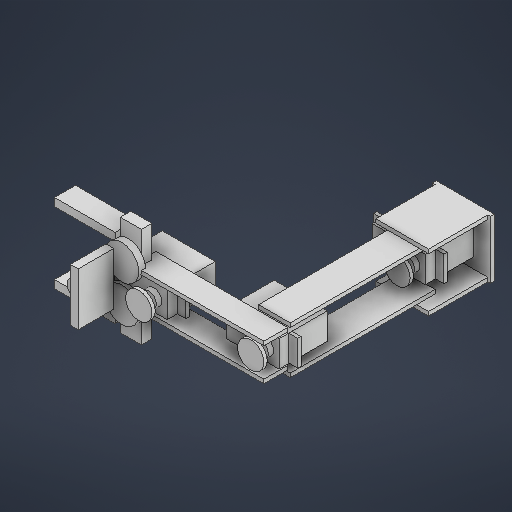
# Autodesk Inventor part: 05_Canh_Tay_3xMG996R_180_Kep_Banh_Rang_ESP32CAM
Saved by Autodesk Inventor 2027.1 (Build 311270010, 270A)
## iProperties
Created: 2026-11-18
Part Number: 05_Canh_Tay_3xMG996R_180_Kep_Banh_Rang_ESP32CAM
Material: Generic
Document SubType Name: Modeling
Designer: cuong
Density: 1 g/cm^3
Appearance: Default
Author: cuong
Autodesk Inventor part; units mm, degrees
ref_plane "Work Plane1" through (0, 0, 185) normal (0, 0, 1) x (1, 0, 0)
sketch "Sketch1" plane through (0, 0, 185) normal (0, 0, 1) x (1, 0, 0)
  line L0 (23, 103) -> (67, 103)
  line L1 (67, 103) -> (67, 147)
  line L2 (67, 147) -> (23, 147)
  line L3 (23, 147) -> (23, 103)
  constraints: 8 end point, 2 parallel, 1 horizontal, 1 perpendicular
extrude "Extrusion1" add sketch "Sketch1" along normal blind 3
ref_plane "Work Plane2" through (0, 0, 188) normal (0, 0, 1) x (1, 0, 0)
sketch "Sketch2" plane through (0, 0, 188) normal (0, 0, 1) x (1, 0, 0)
  line L0 (25, 103) -> (65, 103)
  line L1 (65, 103) -> (65, 106)
  line L2 (65, 106) -> (25, 106)
  line L3 (25, 106) -> (25, 103)
  constraints: 8 end point, 2 parallel, 1 horizontal, 1 perpendicular
extrude "Extrusion2" add sketch "Sketch2" along normal blind 45
ref_plane "Work Plane3" through (0, 0, 188) normal (0, 0, 1) x (1, 0, 0)
sketch "Sketch3" plane through (0, 0, 188) normal (0, 0, 1) x (1, 0, 0)
  line L0 (25, 144) -> (65, 144)
  line L1 (65, 144) -> (65, 147)
  line L2 (65, 147) -> (25, 147)
  line L3 (25, 147) -> (25, 144)
  constraints: 8 end point, 2 parallel, 1 horizontal, 1 perpendicular
extrude "Extrusion3" add sketch "Sketch3" along normal blind 45
ref_plane "Work Plane4" through (0, 0, 189) normal (0, 0, 1) x (1, 0, 0)
sketch "Sketch4" plane through (0, 0, 189) normal (0, 0, 1) x (1, 0, 0)
  line L0 (14.85, 115) -> (55.15, 115)
  line L1 (55.15, 115) -> (55.15, 135)
  line L2 (55.15, 135) -> (14.85, 135)
  line L3 (14.85, 135) -> (14.85, 115)
  constraints: 8 end point, 2 parallel, 1 horizontal, 1 perpendicular
extrude "Extrusion4" add sketch "Sketch4" along normal blind 36.6
ref_plane "Work Plane5" through (0, 0, 215.6) normal (0, 0, 1) x (1, 0, 0)
sketch "Sketch5" plane through (0, 0, 215.6) normal (0, 0, 1) x (1, 0, 0)
  line L0 (8.2, 115.25) -> (61.8, 115.25)
  line L1 (61.8, 115.25) -> (61.8, 134.75)
  line L2 (61.8, 134.75) -> (8.2, 134.75)
  line L3 (8.2, 134.75) -> (8.2, 115.25)
  constraints: 8 end point, 2 parallel, 1 horizontal, 1 perpendicular
extrude "Extrusion5" add sketch "Sketch5" along normal blind 2.5
ref_plane "Work Plane6" through (0, 0, 225.6) normal (0, 0, 1) x (1, 0, 0)
sketch "Sketch6" plane through (0, 0, 225.6) normal (0, 0, 1) x (1, 0, 0)
  circle A0 centre (45, 125) radius 6
  constraints: 1 centre point
extrude "Extrusion6" add sketch "Sketch6" along normal blind 4
ref_plane "Work Plane7" through (0, 0, 229.6) normal (0, 0, 1) x (1, 0, 0)
sketch "Sketch7" plane through (0, 0, 229.6) normal (0, 0, 1) x (1, 0, 0)
  circle A0 centre (45, 125) radius 3
  constraints: 1 centre point
extrude "Extrusion7" add sketch "Sketch7" along normal blind 7
ref_plane "Work Plane8" through (0, 0, 234.5) normal (0, 0, 1) x (1, 0, 0)
sketch "Sketch8" plane through (0, 0, 234.5) normal (0, 0, 1) x (1, 0, 0)
  circle A0 centre (45, 125) radius 10
  constraints: 1 centre point
extrude "Extrusion8" add sketch "Sketch8" along normal blind 2.5
ref_plane "Work Plane9" through (0, 0, 220) normal (0, 0, 1) x (1, 0, 0)
sketch "Sketch9" plane through (0, 0, 220) normal (0, 0, 1) x (1, 0, 0)
  line L0 (33, 107) -> (57, 107)
  line L1 (57, 107) -> (57, 110)
  line L2 (57, 110) -> (33, 110)
  line L3 (33, 110) -> (33, 107)
  constraints: 8 end point, 2 parallel, 1 horizontal, 1 perpendicular
extrude "Extrusion9" add sketch "Sketch9" along normal blind 110
ref_plane "Work Plane10" through (0, 0, 220) normal (0, 0, 1) x (1, 0, 0)
sketch "Sketch10" plane through (0, 0, 220) normal (0, 0, 1) x (1, 0, 0)
  line L0 (33, 140) -> (57, 140)
  line L1 (57, 140) -> (57, 143)
  line L2 (57, 143) -> (33, 143)
  line L3 (33, 143) -> (33, 140)
  constraints: 8 end point, 2 parallel, 1 horizontal, 1 perpendicular
extrude "Extrusion10" add sketch "Sketch10" along normal blind 110
ref_plane "Work Plane11" through (0, 0, 300) normal (0, 0, 1) x (1, 0, 0)
sketch "Sketch11" plane through (0, 0, 300) normal (0, 0, 1) x (1, 0, 0)
  line L0 (14.85, 115) -> (55.15, 115)
  line L1 (55.15, 115) -> (55.15, 135)
  line L2 (55.15, 135) -> (14.85, 135)
  line L3 (14.85, 135) -> (14.85, 115)
  constraints: 8 end point, 2 parallel, 1 horizontal, 1 perpendicular
extrude "Extrusion11" add sketch "Sketch11" along normal blind 36.6
ref_plane "Work Plane12" through (0, 0, 326.6) normal (0, 0, 1) x (1, 0, 0)
sketch "Sketch12" plane through (0, 0, 326.6) normal (0, 0, 1) x (1, 0, 0)
  line L0 (8.2, 115.25) -> (61.8, 115.25)
  line L1 (61.8, 115.25) -> (61.8, 134.75)
  line L2 (61.8, 134.75) -> (8.2, 134.75)
  line L3 (8.2, 134.75) -> (8.2, 115.25)
  constraints: 8 end point, 2 parallel, 1 horizontal, 1 perpendicular
extrude "Extrusion12" add sketch "Sketch12" along normal blind 2.5
ref_plane "Work Plane13" through (0, 0, 336.6) normal (0, 0, 1) x (1, 0, 0)
sketch "Sketch13" plane through (0, 0, 336.6) normal (0, 0, 1) x (1, 0, 0)
  circle A0 centre (45, 125) radius 6
  constraints: 1 centre point
extrude "Extrusion13" add sketch "Sketch13" along normal blind 4
ref_plane "Work Plane14" through (0, 0, 340.6) normal (0, 0, 1) x (1, 0, 0)
sketch "Sketch14" plane through (0, 0, 340.6) normal (0, 0, 1) x (1, 0, 0)
  circle A0 centre (45, 125) radius 3
  constraints: 1 centre point
extrude "Extrusion14" add sketch "Sketch14" along normal blind 7
ref_plane "Work Plane15" through (0, 0, 345.5) normal (0, 0, 1) x (1, 0, 0)
sketch "Sketch15" plane through (0, 0, 345.5) normal (0, 0, 1) x (1, 0, 0)
  circle A0 centre (45, 125) radius 10
  constraints: 1 centre point
extrude "Extrusion15" add sketch "Sketch15" along normal blind 2.5
ref_plane "Work Plane16" through (0, 0, 330) normal (0, 0, 1) x (1, 0, 0)
sketch "Sketch16" plane through (0, 0, 330) normal (0, 0, 1) x (1, 0, 0)
  line L0 (-45, 111) -> (55, 111)
  line L1 (55, 111) -> (55, 114)
  line L2 (55, 114) -> (-45, 114)
  line L3 (-45, 114) -> (-45, 111)
  constraints: 8 end point, 2 parallel, 1 horizontal, 1 perpendicular
extrude "Extrusion16" add sketch "Sketch16" along normal blind 18
ref_plane "Work Plane17" through (0, 0, 330) normal (0, 0, 1) x (1, 0, 0)
sketch "Sketch17" plane through (0, 0, 330) normal (0, 0, 1) x (1, 0, 0)
  line L0 (-45, 136) -> (55, 136)
  line L1 (55, 136) -> (55, 139)
  line L2 (55, 139) -> (-45, 139)
  line L3 (-45, 139) -> (-45, 136)
  constraints: 8 end point, 2 parallel, 1 horizontal, 1 perpendicular
extrude "Extrusion17" add sketch "Sketch17" along normal blind 18
ref_plane "Work Plane18" through (0, 0, 310) normal (0, 0, 1) x (1, 0, 0)
sketch "Sketch18" plane through (0, 0, 310) normal (0, 0, 1) x (1, 0, 0)
  line L0 (-60.15, 115) -> (-19.85, 115)
  line L1 (-19.85, 115) -> (-19.85, 135)
  line L2 (-19.85, 135) -> (-60.15, 135)
  line L3 (-60.15, 135) -> (-60.15, 115)
  constraints: 8 end point, 2 parallel, 1 horizontal, 1 perpendicular
extrude "Extrusion18" add sketch "Sketch18" along normal blind 36.6
ref_plane "Work Plane19" through (0, 0, 336.6) normal (0, 0, 1) x (1, 0, 0)
sketch "Sketch19" plane through (0, 0, 336.6) normal (0, 0, 1) x (1, 0, 0)
  line L0 (-66.8, 115.25) -> (-13.2, 115.25)
  line L1 (-13.2, 115.25) -> (-13.2, 134.75)
  line L2 (-13.2, 134.75) -> (-66.8, 134.75)
  line L3 (-66.8, 134.75) -> (-66.8, 115.25)
  constraints: 8 end point, 2 parallel, 1 horizontal, 1 perpendicular
extrude "Extrusion19" add sketch "Sketch19" along normal blind 2.5
ref_plane "Work Plane20" through (0, 0, 346.6) normal (0, 0, 1) x (1, 0, 0)
sketch "Sketch20" plane through (0, 0, 346.6) normal (0, 0, 1) x (1, 0, 0)
  circle A0 centre (-30, 125) radius 6
  constraints: 1 centre point
extrude "Extrusion20" add sketch "Sketch20" along normal blind 4
ref_plane "Work Plane21" through (0, 0, 350.6) normal (0, 0, 1) x (1, 0, 0)
sketch "Sketch21" plane through (0, 0, 350.6) normal (0, 0, 1) x (1, 0, 0)
  circle A0 centre (-30, 125) radius 3
  constraints: 1 centre point
extrude "Extrusion21" add sketch "Sketch21" along normal blind 7
ref_plane "Work Plane22" through (0, 0, 355.5) normal (0, 0, 1) x (1, 0, 0)
sketch "Sketch22" plane through (0, 0, 355.5) normal (0, 0, 1) x (1, 0, 0)
  circle A0 centre (-30, 125) radius 10
  constraints: 1 centre point
extrude "Extrusion22" add sketch "Sketch22" along normal blind 2.5
ref_plane "Work Plane23" through (0, 0, 337) normal (0, 0, 1) x (1, 0, 0)
sketch "Sketch23" plane through (0, 0, 337) normal (0, 0, 1) x (1, 0, 0)
  line L0 (-57, 87) -> (-41, 87)
  line L1 (-41, 87) -> (-41, 163)
  line L2 (-41, 163) -> (-57, 163)
  line L3 (-57, 163) -> (-57, 87)
  constraints: 8 end point, 2 parallel, 1 horizontal, 1 perpendicular
extrude "Extrusion23" add sketch "Sketch23" along normal blind 8
ref_plane "Work Plane24" through (0, 0, 345) normal (0, 0, 1) x (1, 0, 0)
sketch "Sketch24" plane through (0, 0, 345) normal (0, 0, 1) x (1, 0, 0)
  circle A0 centre (-51, 111) radius 13
  constraints: 1 centre point
extrude "Extrusion24" add sketch "Sketch24" along normal blind 5
ref_plane "Work Plane25" through (0, 0, 345) normal (0, 0, 1) x (1, 0, 0)
sketch "Sketch25" plane through (0, 0, 345) normal (0, 0, 1) x (1, 0, 0)
  circle A0 centre (-51, 139) radius 13
  constraints: 1 centre point
extrude "Extrusion25" add sketch "Sketch25" along normal blind 5
ref_plane "Work Plane26" through (0, 0, 333) normal (0, 0, 1) x (1, 0, 0)
sketch "Sketch26" plane through (0, 0, 333) normal (0, 0, 1) x (1, 0, 0)
  line L0 (-103, 95) -> (-57, 95)
  line L1 (-57, 95) -> (-57, 101)
  line L2 (-57, 101) -> (-103, 101)
  line L3 (-103, 101) -> (-103, 95)
  constraints: 8 end point, 2 parallel, 1 horizontal, 1 perpendicular
extrude "Extrusion26" add sketch "Sketch26" along normal blind 16
ref_plane "Work Plane27" through (0, 0, 333) normal (0, 0, 1) x (1, 0, 0)
sketch "Sketch27" plane through (0, 0, 333) normal (0, 0, 1) x (1, 0, 0)
  line L0 (-103, 149) -> (-57, 149)
  line L1 (-57, 149) -> (-57, 155)
  line L2 (-57, 155) -> (-103, 155)
  line L3 (-103, 155) -> (-103, 149)
  constraints: 8 end point, 2 parallel, 1 horizontal, 1 perpendicular
extrude "Extrusion27" add sketch "Sketch27" along normal blind 16
ref_plane "Work Plane28" through (0, 0, 350) normal (0, 0, 1) x (1, 0, 0)
sketch "Sketch28" plane through (0, 0, 350) normal (0, 0, 1) x (1, 0, 0)
  line L0 (-63, 105) -> (-57, 105)
  line L1 (-57, 105) -> (-57, 145)
  line L2 (-57, 145) -> (-63, 145)
  line L3 (-63, 145) -> (-63, 105)
  constraints: 8 end point, 2 parallel, 1 horizontal, 1 perpendicular
extrude "Extrusion28" add sketch "Sketch28" along normal blind 27
ref_plane "Work Plane29" through (0, 0, 359) normal (0, 0, 1) x (1, 0, 0)
sketch "Sketch29" plane through (0, 0, 359) normal (0, 0, 1) x (1, 0, 0)
  circle A0 centre (-65, 125) radius 6.5
  constraints: 1 centre point
extrude "Extrusion29" add sketch "Sketch29" along normal blind 12
body "Solid1"
